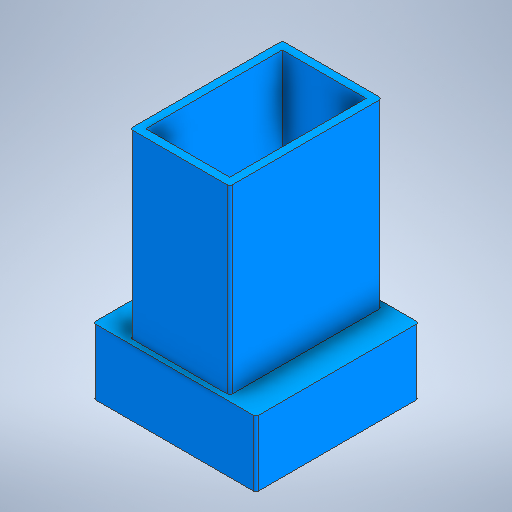
# Autodesk Inventor part: ushalter
Saved by Autodesk Inventor 2026.1 (Build 301233020, 233B)
## iProperties
Created: 2025-11-13
Part Number: ushalter
Material: Generisch
Document SubType Name: Modeling
Designer: Pc
Density: 1 g/cm^3
Appearance: Vorgabe
Author: Pc
Autodesk Inventor part; units mm, degrees
ref_plane "YZ Plane" through (0, 0, 0) normal (1, 0, 0) x (0, 1, 0)
ref_plane "XZ Plane" through (0, 0, 0) normal (0, 1, 0) x (-1, 0, 0)
ref_plane "XY Plane" through (0, 0, 0) normal (0, 0, 1) x (1, 0, 0)
sketch "Skizze1" plane through (0, 0, 0) normal (0, 0, 1) x (1, 0, 0)
  line L0 (-28.05, -28.05) -> (28.05, -28.05)
  line L1 (28.05, -28.05) -> (28.05, 28.05)
  line L2 (28.05, 28.05) -> (-28.05, 28.05)
  line L3 (-28.05, 28.05) -> (-28.05, -28.05)
  line L4 (-28.05, -28.05) -> (28.05, 28.05) construction
  line L5 (28.05, -28.05) -> (-28.05, 28.05) construction
  line L6 (-31.05, -31.05) -> (31.05, -31.05)
  line L7 (31.05, -31.05) -> (31.05, 31.05)
  line L8 (31.05, 31.05) -> (-31.05, 31.05)
  line L9 (-31.05, 31.05) -> (-31.05, -31.05)
  line L10 (-31.05, -31.05) -> (31.05, 31.05) construction
  line L11 (31.05, -31.05) -> (-31.05, 31.05) construction
  point P0 (0, 0)
  dimension "d0" = 56.1
  dimension "d1" = 56.1
  dimension "d2" = 62.1
  dimension "d3" = 62.1
  constraints: 24 end point, 4 midpoint, 4 parallel, 2 horizontal, 2 perpendicular
  measures "d0" distance of L2.end L1.end
  measures "d1" distance of L1.end L0.end
  measures "d2" distance of L8.end L7.end
  measures "d3" distance of L7.end L6.end
extrude "Extrusion1" add sketch "Skizze1" along normal blind 10 and the other way blind 5
sketch "Skizze3" plane through (0, 0, 10) normal (0, 0, 1) x (1, 0, 0)
  line L0 (31.05, 31.05) -> (-31.05, 31.05) projected
  line L1 (-31.05, -31.05) -> (31.05, -31.05)
  line L2 (31.05, -31.05) -> (31.05, 31.05)
  line L3 (31.05, 31.05) -> (-31.05, 31.05)
  line L4 (-31.05, 31.05) -> (-31.05, -31.05)
  line L5 (-31.05, -31.05) -> (31.05, 31.05) construction
  line L6 (31.05, -31.05) -> (-31.05, 31.05) construction
  point P0 (0, 0)
  point P1 (-31.05, 31.05)
  constraints: 12 end point, 2 midpoint, 2 parallel, 1 horizontal, 1 perpendicular
extrude "Extrusion2" add sketch "Skizze3" along normal blind 10
sketch "Skizze4" plane through (0, 0, 20) normal (0, 0, 1) x (1, 0, 0)
  line L0 (-16, 26) -> (16, 26)
  line L1 (16, 26) -> (16, -26)
  line L2 (16, -26) -> (-16, -26)
  line L3 (-16, -26) -> (-16, 26)
  line L4 (-16, 26) -> (16, -26) construction
  line L5 (16, 26) -> (-16, -26) construction
  point P0 (0, 0)
  dimension "d8" = 32
  dimension "d9" = 52
  constraints: 12 end point, 2 midpoint, 2 parallel, 1 horizontal, 1 perpendicular
  measures "d8" distance of L1.end L2.end
  measures "d9" distance of L0.end L1.end
extrude "Extrusion3" cut sketch "Skizze4" against normal through all
sketch "Skizze5" plane through (0, 0, 20) normal (0, 0, 1) x (1, 0, 0)
  line L0 (-19, 29) -> (19, 29)
  line L1 (19, 29) -> (19, -29)
  line L2 (19, -29) -> (-19, -29)
  line L3 (-19, -29) -> (-19, 29)
  line L4 (-19, 29) -> (19, -29) construction
  line L5 (19, 29) -> (-19, -29) construction
  point P0 (0, 0)
  dimension "d12" = 38
  dimension "d13" = 58
  constraints: 12 end point, 2 midpoint, 2 parallel, 1 horizontal, 1 perpendicular
  measures "d12" distance of L1.end L2.end
  measures "d13" distance of L0.end L1.end
extrude "Extrusion4" add sketch "Skizze5" along normal blind 69
sketch "Skizze7" plane through (0, 0, 89) normal (0, 0, 1) x (1, 0, 0)
  line L0 (-16, -26) -> (16, -26) projected
  line L1 (-16, 26) -> (16, 26)
  line L2 (16, 26) -> (16, -26)
  line L3 (16, -26) -> (-16, -26)
  line L4 (-16, -26) -> (-16, 26)
  line L5 (-16, 26) -> (16, -26) construction
  line L6 (16, 26) -> (-16, -26) construction
  point P0 (0, 0)
  constraints: 12 end point, 2 midpoint, 2 parallel, 1 horizontal, 1 perpendicular
extrude "Extrusion5" cut sketch "Skizze7" against normal through all
fillet "Rundung1" radius 1 8 edges at (19, -29, 54.5) (31.05, -31.05, 7.5) (31.05, 31.05, 7.5) (19, 29, 54.5) (-31.05, 31.05, 7.5) (-19, 29, 54.5) (-31.05, -31.05, 7.5) (-19, -29, 54.5)
sketch "Skizze9" plane through (0, 0, 10) normal (0, 0, -1) x (-1, 0, 0)
  line L0 (7, -24) -> (-7, -24)
  line L1 (-7, -24) -> (-7, 24)
  line L2 (-7, 24) -> (7, 24)
  line L3 (7, 24) -> (7, -24)
  line L4 (7, -24) -> (-7, 24) construction
  line L5 (-7, -24) -> (7, 24) construction
  line L6 (16, 26) -> (-16, 26) projected
  line L7 (16, -26) -> (-16, -26)
  line L8 (-16, -26) -> (-16, 26)
  line L9 (-16, 26) -> (16, 26)
  line L10 (16, 26) -> (16, -26)
  line L11 (16, -26) -> (-16, 26) construction
  line L12 (-16, -26) -> (16, 26) construction
  point P0 (0, 0)
  dimension "d21" = 14
  dimension "d22" = 48
  constraints: 24 end point, 4 midpoint, 4 parallel, 2 horizontal, 2 perpendicular
  measures "d21" distance of L1.end L2.end
  measures "d22" distance of L0.end L1.end
extrude "Extrusion6" add sketch "Skizze9" against normal blind 10
chamfer "Fasen1" distance 2 distance2 10 1 edges at (0, 24, 20) measured on face at (13, 8, 20)
chamfer "Fasen2" distance 9 distance2 10 1 edges at (-7, 0, 20) measured on face at (13, 8, 20)
chamfer "Fasen3" distance 9 distance2 10 1 edges at (7, 0, 20) measured on face at (13, -8, 20)
sketch "Skizze10" plane through (0, 0, -5) normal (0, 0, -1) x (-1, 0, 0)
  line L0 (28.25, -28.25) -> (-28.25, -28.25)
  line L1 (-28.25, -28.25) -> (-28.25, 28.25)
  line L2 (-28.25, 28.25) -> (28.25, 28.25)
  line L3 (28.25, 28.25) -> (28.25, -28.25)
  line L4 (-28.05, -28.05) -> (-28.05, 28.05) projected
  line L5 (-28.05, 28.05) -> (28.05, 28.05) projected
  line L6 (28.05, 28.05) -> (28.05, -28.05) projected
  line L7 (28.05, -28.05) -> (-28.05, -28.05) projected
  point P0 (0, 0)
  dimension "d34" = 0.2
  dimension "d35" = 0.2
  dimension "d36" = 0.2
  dimension "d37" = 0.2
  constraints: 8 end point, 2 parallel, 1 horizontal, 1 perpendicular
  measures "d34" distance between parallel lines of L1 L4
  measures "d35" distance between parallel lines of L5 L2
  measures "d36" distance between parallel lines of L6 L3
  measures "d37" distance between parallel lines of L7 L0
extrude "Extrusion7" cut sketch "Skizze10" against normal up to surface (15 mm away)
equation "\"d35\" = d34"
equation "\"d36\" = d34"
equation "\"d37\" = d34"
